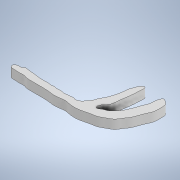
# Autodesk Inventor part: litera_f
Saved by Autodesk Inventor 2022.6 (Build 266554000, 554)
## iProperties
Created: 2024-11-29
Part Number: litera_f
Material: Generic
Document SubType Name: Modeling
Designer: Dragos Macovei
Density: 1 g/cm^3
Appearance: Default
Author: Dragos Macovei
Autodesk Inventor part; units mm, degrees
ref_plane "YZ Plane" through (0, 0, 0) normal (1, 0, 0) x (0, 1, 0)
ref_plane "XZ Plane" through (0, 0, 0) normal (0, 1, 0) x (-1, 0, 0)
ref_plane "XY Plane" through (0, 0, 0) normal (0, 0, 1) x (1, 0, 0)
sketch "Sketch1" plane through (0, 0, 0) normal (0, 1, 0) x (-1, 0, 0)
  line L0 (0, 0) -> (40, 0)
  line L1 (40, 0) -> (40, 40)
  line L2 (40, 40) -> (0, 40)
  line L3 (0, 40) -> (0, 0)
  line L4 (-167.768, 394.3918) -> (195.175, 394.3918) construction
  line L5 (195.175, 394.3918) -> (195.175, -89.5323) construction
  line L6 (195.175, -89.5323) -> (-167.768, -89.5323) construction
  line L7 (-167.768, -89.5323) -> (-167.768, 394.3918) construction
  spline S0 degree 5 poles (38.5274, 23.4909) (38.2891, 23.6552) (37.7599, 23.7777) (36.7802, 23.4848) (35.9014, 24.0966) (33.8824, 23.3824) (33.0717, 24.2895) (31.2228, 24.1153) (29.6596, 24.1909) (27.7568, 24.1393) (26.3119, 24.195) (24.2939, 24.2956) (23.5559, 24.6568) (20.8507, 24.3584) (19.8299, 23.8948) (17.8295, 24.6057) (16.7317, 24.5931) (14.7191, 24.6588) (12.8417, 23.9737) (11.6684, 23.7112) (9.0199, 23.5058) (8.3918, 22.3183) (5.4986, 21.7271) (5.0792, 19.0615) (4.0585, 19.0905) (3.1301, 16.2148) (2.5465, 14.3001) (1.2531, 12.388) (1.7674, 10.4612) (1.378, 8.2014) (2.5501, 7.9686) (3.9088, 6.5539) (4.2579, 8.1121) (4.7967, 9.5035) (4.3369, 10.8555) (5.5441, 12.586) (5.7261, 14.1186) (6.4711, 15.6224) (7.3002, 17.8498) (8.147, 18.4497) (8.9475, 19.254) (9.8374, 20.4077) (10.821, 20.0371) (11.6468, 21.1854) (12.6887, 21.3593) (13.0183, 20.1545) (11.8972, 18.3897) (10.9667, 18.5989) (10.7066, 14.9082) (10.72, 14.5752) (9.9846, 10.4195) (10.2548, 10.0131) (9.8346, 7.8442) (10.1021, 6.2783) (11.1958, 7.3259) (11.662, 7.8607) (11.9057, 9.0751) (12.5366, 10.1724) (12.5102, 11.3723) (12.6213, 12.1851) (12.8706, 13.8032) (13.3895, 15.1776) (13.5517, 15.9227) (14.3636, 17.5111) (14.8946, 18.038) (14.9806, 19.5078) (15.5904, 19.8013) (16.4119, 21.0456) (16.6524, 21.7265) (17.5227, 21.856) (18.2548, 22.6127) (19.3762, 21.4722) (19.7432, 22.3664) (20.9279, 21.796) (22.2363, 22.6616) (23.0713, 21.6182) (24.5277, 22.5119) (25.6208, 21.5929) (26.2956, 22.2771) (27.6731, 21.8128) (28.5691, 21.9154) (30.2772, 22.0615) (31.8612, 21.7238) (33.2049, 21.4737) (34.5054, 21.7235) (36.4451, 20.7956) (36.239, 22.3524) (37.5706, 21.6695) (38.4908, 22.152) (39.0202, 22.4365) (38.9379, 23.0661) (38.7086, 23.366) (38.5274, 23.4909) knots 0 0 0 0 0 0 0.013883 0.023176 0.034908 0.04705 0.059485 0.07192 0.08465 0.097142 0.109908 0.122462 0.134962 0.147268 0.160027 0.172583 0.185152 0.198031 0.211168 0.224748 0.238342 0.251525 0.26483 0.278749 0.29248 0.306455 0.320838 0.334455 0.346879 0.358135 0.368864 0.37948 0.390592 0.402308 0.415043 0.428213 0.441093 0.45342 0.465275 0.476232 0.486442 0.496222 0.505585 0.515296 0.525245 0.536072 0.5481 0.561926 0.575635 0.589994 0.602901 0.614662 0.624791 0.634668 0.644062 0.653954 0.664092 0.674825 0.685832 0.696604 0.707702 0.718855 0.729569 0.739757 0.750132 0.759834 0.769267 0.778525 0.787874 0.796478 0.80531 0.814728 0.824396 0.834468 0.845061 0.855445 0.865566 0.875651 0.885895 0.896765 0.908287 0.920353 0.93248 0.943663 0.954141 0.964242 0.973354 0.982166 0.989446 1 1 1 1 1 1
  point P0 (35.8351, 23.7794)
  point P1 (34.1523, 23.7313)
  point P2 (32.9504, 24.0198)
  point P3 (31.4119, 24.164)
  point P4 (29.633, 24.164)
  point P5 (27.806, 24.164)
  point P6 (26.1233, 24.2121)
  point P7 (24.5367, 24.3563)
  point P8 (23.2867, 24.5005)
  point P9 (21.1232, 24.3082)
  point P10 (19.5847, 24.164)
  point P11 (17.9981, 24.4525)
  point P12 (16.6519, 24.5967)
  point P13 (14.8249, 24.5005)
  point P14 (12.998, 24.0678)
  point P15 (11.4707, 23.7395)
  point P16 (9.4829, 23.2886)
  point P17 (8.0074, 22.4894)
  point P18 (5.9172, 21.1369)
  point P19 (4.8926, 19.5385)
  point P20 (4.2368, 18.6778)
  point P21 (3.2942, 16.6696)
  point P22 (2.372, 14.2515)
  point P23 (1.6343, 12.1818)
  point P24 (1.5933, 9.9276)
  point P25 (1.8597, 8.3907)
  point P26 (2.7819, 7.612)
  point P27 (3.704, 7.2226)
  point P28 (4.1959, 7.8374)
  point P29 (4.5647, 9.3128)
  point P30 (4.6672, 10.7268)
  point P31 (5.282, 12.4482)
  point P32 (5.8353, 14.0671)
  point P33 (6.5525, 15.9114)
  point P34 (7.5156, 17.7967)
  point P35 (8.2534, 18.5959)
  point P36 (9.0526, 19.4156)
  point P37 (9.9542, 20.1123)
  point P38 (10.8149, 20.3787)
  point P39 (11.778, 21.014)
  point P40 (12.4543, 21.0755)
  point P41 (12.7412, 20.3992)
  point P42 (12.1059, 18.9852)
  point P43 (11.3272, 18.145)
  point P44 (10.7944, 15.8909)
  point P45 (10.569, 13.8416)
  point P46 (10.1645, 10.7225)
  point P47 (10.0828, 9.3194)
  point P48 (10.0337, 7.3565)
  point P49 (10.3772, 6.8494)
  point P50 (11.0151, 7.1929)
  point P51 (11.5549, 7.8963)
  point P52 (11.9475, 8.9432)
  point P53 (12.3892, 10.2027)
  point P54 (12.5364, 11.2659)
  point P55 (12.6345, 12.2147)
  point P56 (12.929, 13.7359)
  point P57 (13.3379, 15.11)
  point P58 (13.7035, 16.1171)
  point P59 (14.3724, 17.3998)
  point P60 (14.8147, 18.3065)
  point P61 (15.1243, 19.3016)
  point P62 (15.6329, 20)
  point P63 (16.3627, 21.0486)
  point P64 (16.8271, 21.6236)
  point P65 (17.4905, 21.9774)
  point P66 (18.3309, 22.1986)
  point P67 (19.2376, 21.9111)
  point P68 (19.7904, 22.0217)
  point P69 (20.7413, 22.088)
  point P70 (22.0903, 22.2428)
  point P71 (23.196, 22.0438)
  point P72 (24.5892, 22.1101)
  point P73 (25.6065, 21.9332)
  point P74 (26.3584, 22.0217)
  point P75 (27.4199, 21.9553)
  point P76 (28.5035, 21.9111)
  point P77 (30.0957, 21.9553)
  point P78 (31.8648, 21.7342)
  point P79 (33.3023, 21.5794)
  point P80 (35.0051, 21.4025)
  point P81 (36.155, 21.4467)
  point P82 (36.5973, 21.8669)
  point P83 (37.5482, 21.9111)
  point P84 (38.5274, 22.1986)
  point P85 (38.8972, 22.7293)
  dimension "d0" = 40
  dimension "d1" = 40
  constraints: 8 end point, 2 parallel, 1 horizontal, 1 perpendicular, 90 other
  measures "d0" distance of L2.end L1.end
  measures "d1" distance of L1.end L0.end
extrude "Extrusion1" add sketch "Sketch1" along normal blind 3 contours S0
body "Solid1"
